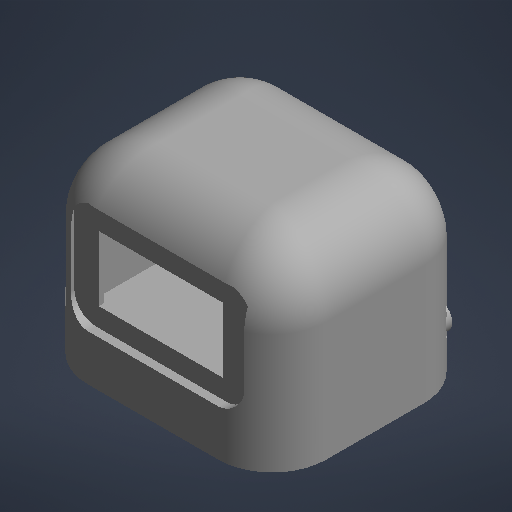
# Autodesk Inventor part: Cabeza_nueva
Saved by Autodesk Inventor 2027 (Build 310192060, 192F)
## iProperties
Part Number: Cabeza_nueva
Material: Genérico
Document SubType Name: Modelado
Designer: rodri
Appearance: Por defecto
Author: rodri
Autodesk Inventor part; units mm, degrees
ref_plane "Plano YZ" through (0, 0, 0) normal (1, 0, 0) x (0, 1, 0)
sketch "Boceto1" plane through (0, 0, 0) normal (0, 1, 0) x (-1, 0, 0)
  line L0 (-22, -15) -> (22, -15)
  line L1 (22, -15) -> (22, 23)
  line L2 (22, 23) -> (-22, 23)
  line L3 (-22, 23) -> (-22, -15)
  constraints: 8 end point, 2 parallel, 1 horizontal, 1 perpendicular
extrude "Extrusión1" add sketch "Boceto1" against normal blind 34
fillet "Empalme1" radius 10 4 edges at (-22, -17, -15) (-22, -17, 23) (22, -17, 23) (22, -17, -15)
fillet "Empalme2" radius 12 8 edges at (19.0711, 0, -12.0711) (0, 0, -15) (19.0711, 0, 20.0711) (0, 0, 23) (-19.0711, 0, 20.0711) (-19.0711, 0, -12.0711) (-22, 0, 4) (22, 0, 4)
ref_plane "Plano de trabajo1" through (0, -2.4, 0) normal (0, 1, 0) x (-1, 0, 0)
sketch "Boceto2" plane through (0, -2.4, 0) normal (0, 1, 0) x (-1, 0, 0)
  line L0 (-19.6, -12.6) -> (19.6, -12.6)
  line L1 (19.6, -12.6) -> (19.6, 20.6)
  line L2 (19.6, 20.6) -> (-19.6, 20.6)
  line L3 (-19.6, 20.6) -> (-19.6, -12.6)
  constraints: 8 end point, 2 parallel, 1 horizontal, 1 perpendicular
extrude "Extrusión2" add sketch "Boceto2" against normal blind 26.2 separate body
fillet "Empalme3" radius 7.6 4 edges at (-19.6, -15.5, -12.6) (-19.6, -15.5, 20.6) (19.6, -15.5, 20.6) (19.6, -15.5, -12.6)
fillet "Empalme4" radius 9.6 8 edges at (17.374, -2.4, -10.374) (0, -2.4, -12.6) (17.374, -2.4, 18.374) (0, -2.4, 20.6) (-17.374, -2.4, 18.374) (-17.374, -2.4, -10.374) (-19.6, -2.4, 4) (19.6, -2.4, 4)
combine bodies "Combinar1" operation type subtract main body 1 bodies to subtract 2
ref_plane "Plano de trabajo2" through (0, 0, 23) normal (0, 0, 1) x (1, 0, 0)
sketch "Boceto3" plane through (0, 0, 23) normal (0, 0, 1) x (1, 0, 0)
  line L0 (-16, -25.5) -> (16, -25.5)
  line L1 (16, -25.5) -> (16, -6.5)
  line L2 (16, -6.5) -> (-16, -6.5)
  line L3 (-16, -6.5) -> (-16, -25.5)
  constraints: 8 end point, 2 parallel, 1 horizontal, 1 perpendicular
extrude "Extrusión3" cut sketch "Boceto3" against normal blind 1.5 bodies 1
fillet "Empalme5" radius 4 2 edges at (16, -25.5, 21.8326) (-16, -25.5, 21.8326)
sketch "Boceto4" plane through (0, 0, 23) normal (0, 0, 1) x (1, 0, 0)
  line L0 (-11.5, -22) -> (11.5, -22)
  line L1 (11.5, -22) -> (11.5, -10)
  line L2 (11.5, -10) -> (-11.5, -10)
  line L3 (-11.5, -10) -> (-11.5, -22)
  constraints: 8 end point, 2 parallel, 1 horizontal, 1 perpendicular
extrude "Extrusión4" cut sketch "Boceto4" against normal blind 4.9 bodies 1
ref_plane "Plano de trabajo3" through (0, -34, 0) normal (0, 1, 0) x (-1, 0, 0)
sketch "Boceto5" plane through (0, -34, 0) normal (0, 1, 0) x (-1, 0, 0)
  circle A0 centre (0, 0) radius 2.5
  constraints: 1 centre point
extrude "Extrusión5" cut sketch "Boceto5" along normal blind 6.4 bodies 1
sketch "Boceto6" plane through (0, -34, 0) normal (0, 1, 0) x (-1, 0, 0)
  circle A0 centre (0, 0) radius 4.45
  constraints: 1 centre point
extrude "Extrusión6" cut sketch "Boceto6" along normal blind 2 bodies 1
sketch "Boceto7" plane through (0, -34, 0) normal (0, 1, 0) x (-1, 0, 0)
  circle A0 centre (0, -8.3) radius 0.9
  circle A1 centre (0, -12.3) radius 0.9
  constraints: 2 centre point
extrude "Extrusión7" cut sketch "Boceto7" along normal blind 6.4 bodies 1
ref_plane "Plano de trabajo4" through (0, 0, -15) normal (0, 0, 1) x (1, 0, 0)
sketch "Boceto8" plane through (0, 0, -15) normal (0, 0, 1) x (1, 0, 0)
  line L0 (-19.6, -28.6) -> (19.6, -28.6)
  line L1 (19.6, -28.6) -> (19.6, -2.4)
  line L2 (19.6, -2.4) -> (-19.6, -2.4)
  line L3 (-19.6, -2.4) -> (-19.6, -28.6)
  constraints: 8 end point, 2 parallel, 1 horizontal, 1 perpendicular
extrude "Extrusión8" cut sketch "Boceto8" along normal blind 2.9 bodies 1
sketch "Boceto9" plane through (0, 0, -15) normal (0, 0, 1) x (1, 0, 0)
  line L0 (-21.1, -30.1) -> (21.1, -30.1)
  line L1 (21.1, -30.1) -> (21.1, -2.4)
  line L2 (21.1, -2.4) -> (-21.1, -2.4)
  line L3 (-21.1, -2.4) -> (-21.1, -30.1)
  constraints: 8 end point, 2 parallel, 1 horizontal, 1 perpendicular
extrude "Extrusión9" cut sketch "Boceto9" along normal blind 2.4 bodies 1
ref_plane "Plano de trabajo5" through (0, 0, -12.6) normal (0, 0, 1) x (1, 0, 0)
sketch "Boceto10" plane through (0, 0, -12.6) normal (0, 0, 1) x (1, 0, 0)
  circle A0 centre (17.1, -26.1) radius 2.5
  circle A1 centre (-17.1, -26.1) radius 2.5
  constraints: 2 centre point
extrude "Extrusión10" add sketch "Boceto10" along normal blind 6 bodies 1
sketch "Boceto11" plane through (0, 0, -12.6) normal (0, 0, 1) x (1, 0, 0)
  circle A0 centre (17.1, -26.1) radius 0.9
  circle A1 centre (-17.1, -26.1) radius 0.9
  constraints: 2 centre point
extrude "Extrusión11" cut sketch "Boceto11" along normal blind 5.5 bodies 1
